Autodesk Fusion 360 part; units mm, degrees
(part 3 of 4)
sketch "Sketch4 (8)" plane through (0, 0, 0) normal (0, 0, 1) x (1, 0, 0) in component "PRT-HANGER"
  circle A0 centre (0, 0) radius 5.75
  dimension "d864" = 11.5
  constraint vertical A0.centre origin
  constraint horizontal A0.centre origin
  measures "d864" diameter of A0
extrude "Extrude4'''''''" cut sketch "Sketch4 (8)" along normal blind 8 from surface at -13 bodies 27 in component "PRT-HANGER"
sketch "Sketch5 (7)" plane through (0, 0, 0) normal (0, 0, 1) x (1, 0, 0) in component "PRT-HANGER"
  circle A0 centre (66, 0) radius 2
  dimension "d868" = 66
  dimension "d869" = 4
  constraint horizontal origin A0.centre
  measures "d868" horizontal distance of origin A0.centre
  measures "d869" diameter of A0
extrude "Extrude5''''''" cut sketch "Sketch5 (7)" along normal blind 14 from surface at -13 bodies 27 in component "PRT-HANGER"
sketch "Sketch6 (6)" plane through (0, 0, 0) normal (0, 0, 1) x (1, 0, 0) in component "PRT-HANGER"
  circle A0 centre (-66, 0) radius 2
  dimension "d873" = 66
  dimension "d874" = 4
  constraint horizontal origin A0.centre
  measures "d873" horizontal distance of origin A0.centre
  measures "d874" diameter of A0
extrude "Extrude6'''''" cut sketch "Sketch6 (6)" along normal blind 14 from surface at -13 bodies 27 in component "PRT-HANGER"
sketch "Sketch1 (14)" plane through (0, 0, 0) normal (1, 0, 0) x (0, 0, -1) in component "Sling cord"
  line L0 (-638.5, -1.5) -> (-638.5, 1.5)
  line L1 (-638.5, 1.5) -> (183, 101.5)
  line L2 (183, 101.5) -> (183, 98.5)
  line L3 (183, 98.5) -> (-638.5, -1.5)
  dimension "d878" = 638.5
  dimension "d880" = 1.5
  dimension "d881" = 1.5
  dimension "d882" = 101.5
  dimension "d883" = 98.5
  constraint vertical L0
  constraint vertical L2
  measures "d878" horizontal distance of origin L0.start
  measures "d880" vertical distance of origin L0.start
  measures "d881" vertical distance of origin L0.end
  measures "d882" vertical distance of origin L1.end
  measures "d883" vertical distance of origin L2.end
extrude "Extrude1''''''''''''''''''" add sketch "Sketch1 (14)" along normal blind 3 from surface at 64.5 separate body makes body 28 in component "Sling cord"
sketch "Sketch2 (11)" plane through (0, 0, 0) normal (1, 0, 0) x (0, 0, -1) in component "Sling cord"
  line L0 (-638.5, -1.5) -> (-638.5, 1.5)
  line L1 (-638.5, 1.5) -> (183, -98.5)
  line L2 (183, -98.5) -> (183, -101.5)
  line L3 (183, -101.5) -> (-638.5, -1.5)
  dimension "d887" = 638.5
  dimension "d889" = 1.5
  dimension "d890" = 1.5
  dimension "d891" = 98.5
  dimension "d892" = 101.5
  constraint vertical L0
  constraint vertical L2
  measures "d887" horizontal distance of origin L0.start
  measures "d889" vertical distance of origin L0.start
  measures "d890" vertical distance of origin L0.end
  measures "d891" vertical distance of origin L1.end
  measures "d892" vertical distance of origin L2.end
extrude "Extrude2''''''''''" add sketch "Sketch2 (11)" along normal blind 3 from surface at 64.5 separate body makes body 29 in component "Sling cord"
sketch "Sketch3 (9)" plane through (0, 0, 0) normal (1, 0, 0) x (0, 0, -1) in component "Sling cord"
  line L0 (-638.5, -1.5) -> (-638.5, 1.5)
  line L1 (-638.5, 1.5) -> (183, 101.5)
  line L2 (183, 101.5) -> (183, 98.5)
  line L3 (183, 98.5) -> (-638.5, -1.5)
  dimension "d896" = 638.5
  dimension "d898" = 1.5
  dimension "d899" = 1.5
  dimension "d900" = 101.5
  dimension "d901" = 98.5
  constraint vertical L0
  constraint vertical L2
  measures "d896" horizontal distance of origin L0.start
  measures "d898" vertical distance of origin L0.start
  measures "d899" vertical distance of origin L0.end
  measures "d900" vertical distance of origin L1.end
  measures "d901" vertical distance of origin L2.end
extrude "Extrude3''''''''" add sketch "Sketch3 (9)" along normal blind 3 from surface at -67.5 separate body makes body 30 in component "Sling cord"
sketch "Sketch4 (9)" plane through (0, 0, 0) normal (1, 0, 0) x (0, 0, -1) in component "Sling cord"
  line L0 (-638.5, -1.5) -> (-638.5, 1.5)
  line L1 (-638.5, 1.5) -> (183, -98.5)
  line L2 (183, -98.5) -> (183, -101.5)
  line L3 (183, -101.5) -> (-638.5, -1.5)
  dimension "d905" = 638.5
  dimension "d907" = 1.5
  dimension "d908" = 1.5
  dimension "d909" = 98.5
  dimension "d910" = 101.5
  constraint vertical L0
  constraint vertical L2
  measures "d905" horizontal distance of origin L0.start
  measures "d907" vertical distance of origin L0.start
  measures "d908" vertical distance of origin L0.end
  measures "d909" vertical distance of origin L1.end
  measures "d910" vertical distance of origin L2.end
extrude "Extrude4''''''''" add sketch "Sketch4 (9)" along normal blind 3 from surface at -67.5 separate body makes body 31 in component "Sling cord"
sketch "Sketch1 (15)" plane through (0, 0, 0) normal (0, 0, 1) x (1, 0, 0) in component "PRT-TRAY"
  line L0 (-70, -133) -> (70, -133)
  line L1 (70, -133) -> (70, 133)
  line L2 (70, 133) -> (-70, 133)
  line L3 (-70, 133) -> (-70, -133)
  dimension "d914" = 133
  dimension "d915" = 70
  dimension "d916" = 133
  dimension "d917" = 70
  constraint horizontal L0
  constraint vertical L1
  constraint horizontal L2
  constraint vertical L3
  measures "d914" vertical distance of origin L0.start
  measures "d915" horizontal distance of origin L0.end
  measures "d916" vertical distance of origin L1.end
  measures "d917" horizontal distance of origin L2.end
extrude "Extrude1'''''''''''''''''''" add sketch "Sketch1 (15)" along normal blind 8 separate body makes body 32 in component "PRT-TRAY"
sketch "Sketch2 (12)" plane through (0, 0, 0) normal (0, 0, 1) x (1, 0, 0) in component "PRT-TRAY"
  line L0 (50.3, 88.45) -> (58.3, 88.45)
  line L1 (58.3, 88.45) -> (58.3, 121.45)
  line L2 (58.3, 121.45) -> (50.3, 121.45)
  line L3 (50.3, 121.45) -> (50.3, 88.45)
  dimension "d920" = 88.45
  dimension "d921" = 58.3
  dimension "d922" = 121.45
  dimension "d923" = 50.3
  constraint horizontal L0
  constraint vertical L1
  constraint horizontal L2
  constraint vertical L3
  measures "d920" vertical distance of origin L0.start
  measures "d921" horizontal distance of origin L0.end
  measures "d922" vertical distance of origin L1.end
  measures "d923" horizontal distance of origin L2.end
extrude "Extrude2'''''''''''" add sketch "Sketch2 (12)" along normal blind 40 from surface at 8 bodies 32 in component "PRT-TRAY"
sketch "Sketch3 (10)" plane through (0, 0, 0) normal (0, 0, 1) x (1, 0, 0) in component "PRT-TRAY"
  line L0 (25.3, 113.45) -> (58.3, 113.45)
  line L1 (58.3, 113.45) -> (58.3, 121.45)
  line L2 (58.3, 121.45) -> (25.3, 121.45)
  line L3 (25.3, 121.45) -> (25.3, 113.45)
  dimension "d927" = 113.45
  dimension "d928" = 58.3
  dimension "d929" = 121.45
  dimension "d930" = 25.3
  constraint horizontal L0
  constraint vertical L1
  constraint horizontal L2
  constraint vertical L3
  measures "d927" vertical distance of origin L0.start
  measures "d928" horizontal distance of origin L0.end
  measures "d929" vertical distance of origin L1.end
  measures "d930" horizontal distance of origin L2.end
extrude "Extrude3'''''''''" add sketch "Sketch3 (10)" along normal blind 40 from surface at 8 bodies 32 in component "PRT-TRAY"
sketch "Sketch4 (10)" plane through (0, 0, 0) normal (0, 0, 1) x (1, 0, 0) in component "PRT-TRAY"
  circle A0 centre (66, 100) radius 2
  dimension "d934" = 66
  dimension "d935" = 100
  dimension "d936" = 4
  measures "d934" horizontal distance of origin A0.centre
  measures "d935" vertical distance of origin A0.centre
  measures "d936" diameter of A0
extrude "Extrude4'''''''''" cut sketch "Sketch4 (10)" along normal blind 10 from surface at -1 bodies 32 in component "PRT-TRAY"
sketch "Sketch5 (8)" plane through (0, 0, 0) normal (0, 0, 1) x (1, 0, 0) in component "PRT-TRAY"
  line L0 (50.3, -121.45) -> (58.3, -121.45)
  line L1 (58.3, -121.45) -> (58.3, -88.45)
  line L2 (58.3, -88.45) -> (50.3, -88.45)
  line L3 (50.3, -88.45) -> (50.3, -121.45)
  dimension "d940" = 121.45
  dimension "d941" = 58.3
  dimension "d942" = 88.45
  dimension "d943" = 50.3
  constraint horizontal L0
  constraint vertical L1
  constraint horizontal L2
  constraint vertical L3
  measures "d940" vertical distance of origin L0.start
  measures "d941" horizontal distance of origin L0.end
  measures "d942" vertical distance of origin L1.end
  measures "d943" horizontal distance of origin L2.end
extrude "Extrude5'''''''" add sketch "Sketch5 (8)" along normal blind 40 from surface at 8 bodies 32 in component "PRT-TRAY"
sketch "Sketch6 (7)" plane through (0, 0, 0) normal (0, 0, 1) x (1, 0, 0) in component "PRT-TRAY"
  line L0 (25.3, -121.45) -> (58.3, -121.45)
  line L1 (58.3, -121.45) -> (58.3, -113.45)
  line L2 (58.3, -113.45) -> (25.3, -113.45)
  line L3 (25.3, -113.45) -> (25.3, -121.45)
  dimension "d947" = 121.45
  dimension "d948" = 58.3
  dimension "d949" = 113.45
  dimension "d950" = 25.3
  constraint horizontal L0
  constraint vertical L1
  constraint horizontal L2
  constraint vertical L3
  measures "d947" vertical distance of origin L0.start
  measures "d948" horizontal distance of origin L0.end
  measures "d949" vertical distance of origin L1.end
  measures "d950" horizontal distance of origin L2.end
extrude "Extrude6''''''" add sketch "Sketch6 (7)" along normal blind 40 from surface at 8 bodies 32 in component "PRT-TRAY"
sketch "Sketch7 (6)" plane through (0, 0, 0) normal (0, 0, 1) x (1, 0, 0) in component "PRT-TRAY"
  circle A0 centre (66, -100) radius 2
  dimension "d954" = 66
  dimension "d955" = 100
  dimension "d956" = 4
  measures "d954" horizontal distance of origin A0.centre
  measures "d955" vertical distance of origin A0.centre
  measures "d956" diameter of A0
extrude "Extrude7'''''" cut sketch "Sketch7 (6)" along normal blind 10 from surface at -1 bodies 32 in component "PRT-TRAY"
sketch "Sketch8 (6)" plane through (0, 0, 0) normal (0, 0, 1) x (1, 0, 0) in component "PRT-TRAY"
  line L0 (-58.3, 88.45) -> (-50.3, 88.45)
  line L1 (-50.3, 88.45) -> (-50.3, 121.45)
  line L2 (-50.3, 121.45) -> (-58.3, 121.45)
  line L3 (-58.3, 121.45) -> (-58.3, 88.45)
  dimension "d960" = 88.45
  dimension "d961" = 50.3
  dimension "d962" = 121.45
  dimension "d963" = 58.3
  constraint horizontal L0
  constraint vertical L1
  constraint horizontal L2
  constraint vertical L3
  measures "d960" vertical distance of origin L0.start
  measures "d961" horizontal distance of origin L0.end
  measures "d962" vertical distance of origin L1.end
  measures "d963" horizontal distance of origin L2.end
extrude "Extrude8'''''" add sketch "Sketch8 (6)" along normal blind 40 from surface at 8 bodies 32 in component "PRT-TRAY"
sketch "Sketch9 (3)" plane through (0, 0, 0) normal (0, 0, 1) x (1, 0, 0) in component "PRT-TRAY"
  line L0 (-58.3, 113.45) -> (-25.3, 113.45)
  line L1 (-25.3, 113.45) -> (-25.3, 121.45)
  line L2 (-25.3, 121.45) -> (-58.3, 121.45)
  line L3 (-58.3, 121.45) -> (-58.3, 113.45)
  dimension "d967" = 113.45
  dimension "d968" = 25.3
  dimension "d969" = 121.45
  dimension "d970" = 58.3
  constraint horizontal L0
  constraint vertical L1
  constraint horizontal L2
  constraint vertical L3
  measures "d967" vertical distance of origin L0.start
  measures "d968" horizontal distance of origin L0.end
  measures "d969" vertical distance of origin L1.end
  measures "d970" horizontal distance of origin L2.end
extrude "Extrude9''" add sketch "Sketch9 (3)" along normal blind 40 from surface at 8 bodies 32 in component "PRT-TRAY"
sketch "Sketch10 (3)" plane through (0, 0, 0) normal (0, 0, 1) x (1, 0, 0) in component "PRT-TRAY"
  circle A0 centre (-66, 100) radius 2
  dimension "d974" = 66
  dimension "d975" = 100
  dimension "d976" = 4
  measures "d974" horizontal distance of origin A0.centre
  measures "d975" vertical distance of origin A0.centre
  measures "d976" diameter of A0
extrude "Extrude10''" cut sketch "Sketch10 (3)" along normal blind 10 from surface at -1 bodies 32 in component "PRT-TRAY"
sketch "Sketch11 (3)" plane through (0, 0, 0) normal (0, 0, 1) x (1, 0, 0) in component "PRT-TRAY"
  line L0 (-58.3, -121.45) -> (-50.3, -121.45)
  line L1 (-50.3, -121.45) -> (-50.3, -88.45)
  line L2 (-50.3, -88.45) -> (-58.3, -88.45)
  line L3 (-58.3, -88.45) -> (-58.3, -121.45)
  dimension "d980" = 121.45
  dimension "d981" = 50.3
  dimension "d982" = 88.45
  dimension "d983" = 58.3
  constraint horizontal L0
  constraint vertical L1
  constraint horizontal L2
  constraint vertical L3
  measures "d980" vertical distance of origin L0.start
  measures "d981" horizontal distance of origin L0.end
  measures "d982" vertical distance of origin L1.end
  measures "d983" horizontal distance of origin L2.end
extrude "Extrude11''" add sketch "Sketch11 (3)" along normal blind 40 from surface at 8 bodies 32 in component "PRT-TRAY"
sketch "Sketch12 (3)" plane through (0, 0, 0) normal (0, 0, 1) x (1, 0, 0) in component "PRT-TRAY"
  line L0 (-58.3, -121.45) -> (-25.3, -121.45)
  line L1 (-25.3, -121.45) -> (-25.3, -113.45)
  line L2 (-25.3, -113.45) -> (-58.3, -113.45)
  line L3 (-58.3, -113.45) -> (-58.3, -121.45)
  dimension "d987" = 121.45
  dimension "d988" = 25.3
  dimension "d989" = 113.45
  dimension "d990" = 58.3
  constraint horizontal L0
  constraint vertical L1
  constraint horizontal L2
  constraint vertical L3
  measures "d987" vertical distance of origin L0.start
  measures "d988" horizontal distance of origin L0.end
  measures "d989" vertical distance of origin L1.end
  measures "d990" horizontal distance of origin L2.end
extrude "Extrude12''" add sketch "Sketch12 (3)" along normal blind 40 from surface at 8 bodies 32 in component "PRT-TRAY"
sketch "Sketch13 (3)" plane through (0, 0, 0) normal (0, 0, 1) x (1, 0, 0) in component "PRT-TRAY"
  circle A0 centre (-66, -100) radius 2
  dimension "d994" = 66
  dimension "d995" = 100
  dimension "d996" = 4
  measures "d994" horizontal distance of origin A0.centre
  measures "d995" vertical distance of origin A0.centre
  measures "d996" diameter of A0
extrude "Extrude13''" cut sketch "Sketch13 (3)" along normal blind 10 from surface at -1 bodies 32 in component "PRT-TRAY"
sketch "Sketch1 (16)" plane through (0, 0, 0) normal (0, 0, 1) x (1, 0, 0) in component "6U envelope (reference)"
  line L0 (-50, -113.15) -> (50, -113.15)
  line L1 (50, -113.15) -> (50, 113.15)
  line L2 (50, 113.15) -> (-50, 113.15)
  line L3 (-50, 113.15) -> (-50, -113.15)
  dimension "d1000" = 113.15
  dimension "d1001" = 50
  dimension "d1002" = 113.15
  dimension "d1003" = 50
  constraint horizontal L0
  constraint vertical L1
  constraint horizontal L2
  constraint vertical L3
  measures "d1000" vertical distance of origin L0.start
  measures "d1001" horizontal distance of origin L0.end
  measures "d1002" vertical distance of origin L1.end
  measures "d1003" horizontal distance of origin L2.end
extrude "Extrude1''''''''''''''''''''" add sketch "Sketch1 (16)" along normal blind 366 from surface at -183 separate body makes body 33 in component "6U envelope (reference)"
sketch "Sketch1 (17)" plane through (0, 0, 0) normal (0, 0, 1) x (1, 0, 0) in component "Working volume 6U+10 (reference)"
  line L0 (-60, -123.15) -> (60, -123.15)
  line L1 (60, -123.15) -> (60, 123.15)
  line L2 (60, 123.15) -> (-60, 123.15)
  line L3 (-60, 123.15) -> (-60, -123.15)
  dimension "d1007" = 123.15
  dimension "d1008" = 60
  dimension "d1009" = 123.15
  dimension "d1010" = 60
  constraint horizontal L0
  constraint vertical L1
  constraint horizontal L2
  constraint vertical L3
  measures "d1007" vertical distance of origin L0.start
  measures "d1008" horizontal distance of origin L0.end
  measures "d1009" vertical distance of origin L1.end
  measures "d1010" horizontal distance of origin L2.end
extrude "Extrude1'''''''''''''''''''''" add sketch "Sketch1 (17)" along normal blind 386 from surface at -193 separate body makes body 34 in component "Working volume 6U+10 (reference)"
sketch "Sketch1 (18)" plane through (0, 0, 0) normal (0, 0, 1) x (1, 0, 0) in component "PRT-GAUGE-X"
  line L0 (0, -20) -> (251.25, -20)
  line L1 (251.25, -20) -> (251.25, 20)
  line L2 (251.25, 20) -> (0, 20)
  line L3 (0, 20) -> (0, -20)
  dimension "d1014" = 20
  dimension "d1015" = 251.25
  dimension "d1016" = 20
  constraint horizontal L0
  constraint vertical L1
  constraint horizontal L2
  constraint vertical L3
  constraint vertical origin L2.end
  measures "d1014" vertical distance of origin L0.start
  measures "d1015" horizontal distance of origin L0.end
  measures "d1016" vertical distance of origin L1.end
extrude "Extrude1''''''''''''''''''''''" add sketch "Sketch1 (18)" along normal blind 10 separate body makes body 35 in component "PRT-GAUGE-X"
sketch "Sketch2 (13)" plane through (0, 0, 0) normal (0, 0, 1) x (1, 0, 0) in component "PRT-GAUGE-X"
  line L0 (0, -3.8) -> (251.25, -3.8)
  line L1 (251.25, -3.8) -> (251.25, 3.8)
  line L2 (251.25, 3.8) -> (0, 3.8)
  line L3 (0, 3.8) -> (0, -3.8)
  dimension "d1019" = 3.8
  dimension "d1020" = 251.25
  dimension "d1021" = 3.8
  constraint horizontal L0
  constraint vertical L1
  constraint horizontal L2
  constraint vertical L3
  constraint vertical origin L2.end
  measures "d1019" vertical distance of origin L0.start
  measures "d1020" horizontal distance of origin L0.end
  measures "d1021" vertical distance of origin L1.end
extrude "Extrude2''''''''''''" add sketch "Sketch2 (13)" along normal blind 3.8 from surface at -3.8 bodies 35 in component "PRT-GAUGE-X"
sketch "Sketch1 (19)" plane through (0, 0, 0) normal (0, 0, 1) x (1, 0, 0) in component "PRT-GAUGE-Y"
  line L0 (0, -20) -> (271, -20)
  line L1 (271, -20) -> (271, 20)
  line L2 (271, 20) -> (0, 20)
  line L3 (0, 20) -> (0, -20)
  dimension "d1025" = 20
  dimension "d1026" = 271
  dimension "d1027" = 20
  constraint horizontal L0
  constraint vertical L1
  constraint horizontal L2
  constraint vertical L3
  constraint vertical origin L2.end
  measures "d1025" vertical distance of origin L0.start
  measures "d1026" horizontal distance of origin L0.end
  measures "d1027" vertical distance of origin L1.end
extrude "Extrude1'''''''''''''''''''''''" add sketch "Sketch1 (19)" along normal blind 10 separate body makes body 36 in component "PRT-GAUGE-Y"
sketch "Sketch2 (14)" plane through (0, 0, 0) normal (0, 0, 1) x (1, 0, 0) in component "PRT-GAUGE-Y"
  line L0 (0, -3.8) -> (271, -3.8)
  line L1 (271, -3.8) -> (271, 3.8)
  line L2 (271, 3.8) -> (0, 3.8)
  line L3 (0, 3.8) -> (0, -3.8)
  dimension "d1030" = 3.8
  dimension "d1031" = 271
  dimension "d1032" = 3.8
  constraint horizontal L0
  constraint vertical L1
  constraint horizontal L2
  constraint vertical L3
  constraint vertical origin L2.end
  measures "d1030" vertical distance of origin L0.start
  measures "d1031" horizontal distance of origin L0.end
  measures "d1032" vertical distance of origin L1.end
extrude "Extrude2'''''''''''''" add sketch "Sketch2 (14)" along normal blind 3.8 from surface at -3.8 bodies 36 in component "PRT-GAUGE-Y"
sketch "Sketch1 (20)" plane through (0, 0, 0) normal (0, 0, 1) x (1, 0, 0) in component "PRT-GAUGE-Z"
  line L0 (0, -20) -> (187.5, -20)
  line L1 (187.5, -20) -> (187.5, 20)
  line L2 (187.5, 20) -> (0, 20)
  line L3 (0, 20) -> (0, -20)
  dimension "d1036" = 20
  dimension "d1037" = 187.5
  dimension "d1038" = 20
  constraint horizontal L0
  constraint vertical L1
  constraint horizontal L2
  constraint vertical L3
  constraint vertical origin L2.end
  measures "d1036" vertical distance of origin L0.start
  measures "d1037" horizontal distance of origin L0.end
  measures "d1038" vertical distance of origin L1.end
extrude "Extrude1''''''''''''''''''''''''" add sketch "Sketch1 (20)" along normal blind 10 separate body makes body 37 in component "PRT-GAUGE-Z"
sketch "Sketch2 (15)" plane through (0, 0, 0) normal (0, 0, 1) x (1, 0, 0) in component "PRT-GAUGE-Z"
  line L0 (0, -3.8) -> (187.5, -3.8)
  line L1 (187.5, -3.8) -> (187.5, 3.8)
  line L2 (187.5, 3.8) -> (0, 3.8)
  line L3 (0, 3.8) -> (0, -3.8)
  dimension "d1041" = 3.8
  dimension "d1042" = 187.5
  dimension "d1043" = 3.8
  constraint horizontal L0
  constraint vertical L1
  constraint horizontal L2
  constraint vertical L3
  constraint vertical origin L2.end
  measures "d1041" vertical distance of origin L0.start
  measures "d1042" horizontal distance of origin L0.end
  measures "d1043" vertical distance of origin L1.end
extrude "Extrude2''''''''''''''" add sketch "Sketch2 (15)" along normal blind 3.8 from surface at -3.8 bodies 37 in component "PRT-GAUGE-Z"
sketch "Sketch1 (21)" plane through (0, 0, 0) normal (0, 0, 1) x (1, 0, 0) in component "PRT-GAUGE-C"
  line L0 (0, -20) -> (187, -20)
  line L1 (187, -20) -> (187, 20)
  line L2 (187, 20) -> (0, 20)
  line L3 (0, 20) -> (0, -20)
  dimension "d1047" = 20
  dimension "d1048" = 187
  dimension "d1049" = 20
  constraint horizontal L0
  constraint vertical L1
  constraint horizontal L2
  constraint vertical L3
  constraint vertical origin L2.end
  measures "d1047" vertical distance of origin L0.start
  measures "d1048" horizontal distance of origin L0.end
  measures "d1049" vertical distance of origin L1.end
extrude "Extrude1'''''''''''''''''''''''''" add sketch "Sketch1 (21)" along normal blind 10 separate body makes body 38 in component "PRT-GAUGE-C"
sketch "Sketch2 (16)" plane through (0, 0, 0) normal (0, 0, 1) x (1, 0, 0) in component "PRT-GAUGE-C"
  line L0 (0, -3.8) -> (187, -3.8)
  line L1 (187, -3.8) -> (187, 3.8)
  line L2 (187, 3.8) -> (0, 3.8)
  line L3 (0, 3.8) -> (0, -3.8)
  dimension "d1052" = 3.8
  dimension "d1053" = 187
  dimension "d1054" = 3.8
  constraint horizontal L0
  constraint vertical L1
  constraint horizontal L2
  constraint vertical L3
  constraint vertical origin L2.end
  measures "d1052" vertical distance of origin L0.start
  measures "d1053" horizontal distance of origin L0.end
  measures "d1054" vertical distance of origin L1.end
extrude "Extrude2'''''''''''''''" add sketch "Sketch2 (16)" along normal blind 3.8 from surface at -3.8 bodies 38 in component "PRT-GAUGE-C"
ref_plane "WorkPlane1" through (0, 383.5, 0) normal (0, 1, 0) x (0, 0, 1)
ref_plane "WorkPlane2" through (0, 0, 425) normal (0, 0, 1) x (1, 0, 0)
component "6575N25 cross-section" placed x (1, 0, 0) y (0, 1, 0) z (0, 0, 1) at (0, 0, 0)
component "Pair X" placed x (1, 0, 0) y (0, 1, 0) z (0, 0, 1) at (0, 0, 0)
component "Pair Y" placed x (1, 0, 0) y (0, 1, 0) z (0, 0, 1) at (0, 0, 0)
component "Pair Z" placed x (1, 0, 0) y (0, 1, 0) z (0, 0, 1) at (0, 0, 0)
component "Crossing mounts" placed x (1, 0, 0) y (0, 1, 0) z (0, 0, 1) at (0, 0, 0)
component "Stand" placed x (1, 0, 0) y (0, 1, 0) z (0, 0, 1) at (0, 0, 0)
component "CubeSat hanger" placed x (1, 0, 0) y (0, 1, 0) z (0, 0, 1) at (0, 0, 0)
component "Reference (not built)" placed x (1, 0, 0) y (0, 1, 0) z (0, 0, 1) at (0, 0, 0)
component "Assembly gauges (removable)" placed x (1, 0, 0) y (0, 1, 0) z (0, 0, 1) at (0, 0, 0)
component "Coil X" placed x (1, 0, 0) y (0, 1, 0) z (0, 0, 1) at (0, 0, 0) in component "Pair X"
component "Coil X" placed x (1, 0, 0) y (0, 1, 0) z (0, 0, 1) at (0, 0, 0) in component "Pair X"
component "6575N25 x 1301" placed x (1, 0, 0) y (0, 1, 0) z (0, 0, 1) at (0, 0, 0) in component "Coil X"
component "6575N25 x 1301" placed x (1, 0, 0) y (0, 1, 0) z (0, 0, 1) at (0, 0, 0) in component "Coil X"
component "6575N25 x 1301" placed x (1, 0, 0) y (0, 1, 0) z (0, 0, 1) at (0, 0, 0) in component "Coil X"
component "6575N25 x 1301" placed x (1, 0, 0) y (0, 1, 0) z (0, 0, 1) at (0, 0, 0) in component "Coil X"
component "PRT-CORNER-STEP" placed x (1, 0, 0) y (0, 1, 0) z (0, 0, 1) at (0, 0, 0) in component "Coil X"
component "5537T586" placed x (1, 0, 0) y (0, 1, 0) z (0, 0, 1) at (0, 0, 0) in component "Coil X"
component "PRT-CORNER" placed x (1, 0, 0) y (0, 1, 0) z (0, 0, 1) at (0, 0, 0) in component "Coil X"
component "5537T586" placed x (1, 0, 0) y (0, 1, 0) z (0, 0, 1) at (0, 0, 0) in component "Coil X"
component "PRT-CORNER" placed x (1, 0, 0) y (0, 1, 0) z (0, 0, 1) at (0, 0, 0) in component "Coil X"
component "5537T586" placed x (1, 0, 0) y (0, 1, 0) z (0, 0, 1) at (0, 0, 0) in component "Coil X"
component "PRT-CORNER" placed x (1, 0, 0) y (0, 1, 0) z (0, 0, 1) at (0, 0, 0) in component "Coil X"
component "5537T586" placed x (1, 0, 0) y (0, 1, 0) z (0, 0, 1) at (0, 0, 0) in component "Coil X"
component "Winding X (40 t AWG18)" placed x (1, 0, 0) y (0, 1, 0) z (0, 0, 1) at (0, 0, 0) in component "Coil X"
component "PRT-CLIP" placed x (1, 0, 0) y (0, 1, 0) z (0, 0, 1) at (0, 0, 0) in component "Coil X"
component "PRT-CLIP" placed x (1, 0, 0) y (0, 1, 0) z (0, 0, 1) at (0, 0, 0) in component "Coil X"
component "PRT-CLIP" placed x (1, 0, 0) y (0, 1, 0) z (0, 0, 1) at (0, 0, 0) in component "Coil X"
component "PRT-CLIP" placed x (1, 0, 0) y (0, 1, 0) z (0, 0, 1) at (0, 0, 0) in component "Coil X"
component "PRT-CLIP" placed x (1, 0, 0) y (0, 1, 0) z (0, 0, 1) at (0, 0, 0) in component "Coil X"
component "PRT-CLIP" placed x (1, 0, 0) y (0, 1, 0) z (0, 0, 1) at (0, 0, 0) in component "Coil X"
component "PRT-CLIP" placed x (1, 0, 0) y (0, 1, 0) z (0, 0, 1) at (0, 0, 0) in component "Coil X"
component "PRT-CLIP" placed x (1, 0, 0) y (0, 1, 0) z (0, 0, 1) at (0, 0, 0) in component "Coil X"
component "PRT-CLIP" placed x (1, 0, 0) y (0, 1, 0) z (0, 0, 1) at (0, 0, 0) in component "Coil X"
component "PRT-CLIP" placed x (1, 0, 0) y (0, 1, 0) z (0, 0, 1) at (0, 0, 0) in component "Coil X"
component "PRT-CLIP" placed x (1, 0, 0) y (0, 1, 0) z (0, 0, 1) at (0, 0, 0) in component "Coil X"
component "PRT-CLIP" placed x (1, 0, 0) y (0, 1, 0) z (0, 0, 1) at (0, 0, 0) in component "Coil X"
component "Leads X" placed x (1, 0, 0) y (0, 1, 0) z (0, 0, 1) at (0, 0, 0) in component "Coil X"
component "PRT-TIE" placed x (1, 0, 0) y (0, 1, 0) z (0, 0, 1) at (0, 0, 0) in component "Leads X"
component "Anderson 1327G6" placed x (1, 0, 0) y (0, 1, 0) z (0, 0, 1) at (0, 0, 0) in component "Leads X"
component "Anderson 1327" placed x (1, 0, 0) y (0, 1, 0) z (0, 0, 1) at (0, 0, 0) in component "Leads X"
component "Coil Y" placed x (1, 0, 0) y (0, 1, 0) z (0, 0, 1) at (0, 0, 0) in component "Pair Y"
component "Coil Y" placed x (1, 0, 0) y (0, 1, 0) z (0, 0, 1) at (0, 0, 0) in component "Pair Y"
component "6575N25 x 1385" placed x (1, 0, 0) y (0, 1, 0) z (0, 0, 1) at (0, 0, 0) in component "Coil Y"
component "6575N25 x 1385" placed x (1, 0, 0) y (0, 1, 0) z (0, 0, 1) at (0, 0, 0) in component "Coil Y"
component "6575N25 x 1385" placed x (1, 0, 0) y (0, 1, 0) z (0, 0, 1) at (0, 0, 0) in component "Coil Y"
component "6575N25 x 1385" placed x (1, 0, 0) y (0, 1, 0) z (0, 0, 1) at (0, 0, 0) in component "Coil Y"
component "PRT-CORNER-STEP" placed x (1, 0, 0) y (0, 1, 0) z (0, 0, 1) at (0, 0, 0) in component "Coil Y"
component "5537T586" placed x (1, 0, 0) y (0, 1, 0) z (0, 0, 1) at (0, 0, 0) in component "Coil Y"
component "PRT-CORNER" placed x (1, 0, 0) y (0, 1, 0) z (0, 0, 1) at (0, 0, 0) in component "Coil Y"
component "5537T586" placed x (1, 0, 0) y (0, 1, 0) z (0, 0, 1) at (0, 0, 0) in component "Coil Y"
component "PRT-CORNER" placed x (1, 0, 0) y (0, 1, 0) z (0, 0, 1) at (0, 0, 0) in component "Coil Y"
component "5537T586" placed x (1, 0, 0) y (0, 1, 0) z (0, 0, 1) at (0, 0, 0) in component "Coil Y"
component "PRT-CORNER" placed x (1, 0, 0) y (0, 1, 0) z (0, 0, 1) at (0, 0, 0) in component "Coil Y"
component "5537T586" placed x (1, 0, 0) y (0, 1, 0) z (0, 0, 1) at (0, 0, 0) in component "Coil Y"
component "Winding Y (40 t AWG18)" placed x (1, 0, 0) y (0, 1, 0) z (0, 0, 1) at (0, 0, 0) in component "Coil Y"
component "PRT-CLIP" placed x (1, 0, 0) y (0, 1, 0) z (0, 0, 1) at (0, 0, 0) in component "Coil Y"
component "PRT-CLIP" placed x (1, 0, 0) y (0, 1, 0) z (0, 0, 1) at (0, 0, 0) in component "Coil Y"
component "PRT-CLIP" placed x (1, 0, 0) y (0, 1, 0) z (0, 0, 1) at (0, 0, 0) in component "Coil Y"
component "PRT-CLIP" placed x (1, 0, 0) y (0, 1, 0) z (0, 0, 1) at (0, 0, 0) in component "Coil Y"
component "PRT-CLIP" placed x (1, 0, 0) y (0, 1, 0) z (0, 0, 1) at (0, 0, 0) in component "Coil Y"
component "PRT-CLIP" placed x (1, 0, 0) y (0, 1, 0) z (0, 0, 1) at (0, 0, 0) in component "Coil Y"
component "PRT-CLIP" placed x (1, 0, 0) y (0, 1, 0) z (0, 0, 1) at (0, 0, 0) in component "Coil Y"
component "PRT-CLIP" placed x (1, 0, 0) y (0, 1, 0) z (0, 0, 1) at (0, 0, 0) in component "Coil Y"
component "PRT-CLIP" placed x (1, 0, 0) y (0, 1, 0) z (0, 0, 1) at (0, 0, 0) in component "Coil Y"
component "PRT-CLIP" placed x (1, 0, 0) y (0, 1, 0) z (0, 0, 1) at (0, 0, 0) in component "Coil Y"
component "PRT-CLIP" placed x (1, 0, 0) y (0, 1, 0) z (0, 0, 1) at (0, 0, 0) in component "Coil Y"
component "PRT-CLIP" placed x (1, 0, 0) y (0, 1, 0) z (0, 0, 1) at (0, 0, 0) in component "Coil Y"
component "Leads Y" placed x (1, 0, 0) y (0, 1, 0) z (0, 0, 1) at (0, 0, 0) in component "Coil Y"
component "PRT-TIE" placed x (1, 0, 0) y (0, 1, 0) z (0, 0, 1) at (0, 0, 0) in component "Leads Y"
component "Anderson 1327G6" placed x (1, 0, 0) y (0, 1, 0) z (0, 0, 1) at (0, 0, 0) in component "Leads Y"
component "Anderson 1327" placed x (1, 0, 0) y (0, 1, 0) z (0, 0, 1) at (0, 0, 0) in component "Leads Y"
component "Coil Z" placed x (1, 0, 0) y (0, 1, 0) z (0, 0, 1) at (0, 0, 0) in component "Pair Z"
component "Coil Z" placed x (1, 0, 0) y (0, 1, 0) z (0, 0, 1) at (0, 0, 0) in component "Pair Z"
component "6575N25 x 1469" placed x (1, 0, 0) y (0, 1, 0) z (0, 0, 1) at (0, 0, 0) in component "Coil Z"
component "6575N25 x 1469" placed x (1, 0, 0) y (0, 1, 0) z (0, 0, 1) at (0, 0, 0) in component "Coil Z"
component "6575N25 x 1469" placed x (1, 0, 0) y (0, 1, 0) z (0, 0, 1) at (0, 0, 0) in component "Coil Z"
component "6575N25 x 1469" placed x (1, 0, 0) y (0, 1, 0) z (0, 0, 1) at (0, 0, 0) in component "Coil Z"
component "PRT-CORNER-STEP" placed x (1, 0, 0) y (0, 1, 0) z (0, 0, 1) at (0, 0, 0) in component "Coil Z"
component "5537T586" placed x (1, 0, 0) y (0, 1, 0) z (0, 0, 1) at (0, 0, 0) in component "Coil Z"
component "PRT-CORNER" placed x (1, 0, 0) y (0, 1, 0) z (0, 0, 1) at (0, 0, 0) in component "Coil Z"
component "5537T586" placed x (1, 0, 0) y (0, 1, 0) z (0, 0, 1) at (0, 0, 0) in component "Coil Z"
component "PRT-CORNER" placed x (1, 0, 0) y (0, 1, 0) z (0, 0, 1) at (0, 0, 0) in component "Coil Z"
component "5537T586" placed x (1, 0, 0) y (0, 1, 0) z (0, 0, 1) at (0, 0, 0) in component "Coil Z"
component "PRT-CORNER" placed x (1, 0, 0) y (0, 1, 0) z (0, 0, 1) at (0, 0, 0) in component "Coil Z"
component "5537T586" placed x (1, 0, 0) y (0, 1, 0) z (0, 0, 1) at (0, 0, 0) in component "Coil Z"
component "Winding Z (40 t AWG18)" placed x (1, 0, 0) y (0, 1, 0) z (0, 0, 1) at (0, 0, 0) in component "Coil Z"
component "PRT-CLIP" placed x (1, 0, 0) y (0, 1, 0) z (0, 0, 1) at (0, 0, 0) in component "Coil Z"
component "PRT-CLIP" placed x (1, 0, 0) y (0, 1, 0) z (0, 0, 1) at (0, 0, 0) in component "Coil Z"
component "PRT-CLIP" placed x (1, 0, 0) y (0, 1, 0) z (0, 0, 1) at (0, 0, 0) in component "Coil Z"
component "PRT-CLIP" placed x (1, 0, 0) y (0, 1, 0) z (0, 0, 1) at (0, 0, 0) in component "Coil Z"
component "PRT-CLIP" placed x (1, 0, 0) y (0, 1, 0) z (0, 0, 1) at (0, 0, 0) in component "Coil Z"
component "PRT-CLIP" placed x (1, 0, 0) y (0, 1, 0) z (0, 0, 1) at (0, 0, 0) in component "Coil Z"
component "PRT-CLIP" placed x (1, 0, 0) y (0, 1, 0) z (0, 0, 1) at (0, 0, 0) in component "Coil Z"
component "PRT-CLIP" placed x (1, 0, 0) y (0, 1, 0) z (0, 0, 1) at (0, 0, 0) in component "Coil Z"
component "PRT-CLIP" placed x (1, 0, 0) y (0, 1, 0) z (0, 0, 1) at (0, 0, 0) in component "Coil Z"
component "PRT-CLIP" placed x (1, 0, 0) y (0, 1, 0) z (0, 0, 1) at (0, 0, 0) in component "Coil Z"
component "PRT-CLIP" placed x (1, 0, 0) y (0, 1, 0) z (0, 0, 1) at (0, 0, 0) in component "Coil Z"
component "PRT-CLIP" placed x (1, 0, 0) y (0, 1, 0) z (0, 0, 1) at (0, 0, 0) in component "Coil Z"
component "Leads Z" placed x (1, 0, 0) y (0, 1, 0) z (0, 0, 1) at (0, 0, 0) in component "Coil Z"
component "PRT-TIE" placed x (1, 0, 0) y (0, 1, 0) z (0, 0, 1) at (0, 0, 0) in component "Leads Z"
component "Anderson 1327G6" placed x (1, 0, 0) y (0, 1, 0) z (0, 0, 1) at (0, 0, 0) in component "Leads Z"
component "Anderson 1327" placed x (1, 0, 0) y (0, 1, 0) z (0, 0, 1) at (0, 0, 0) in component "Leads Z"
component "5537T586" placed x (1, 0, 0) y (0, 1, 0) z (0, 0, 1) at (0, 0, 0) in component "Crossing mounts"
component "PRT-SHIM" placed x (1, 0, 0) y (0, 1, 0) z (0, 0, 1) at (0, 0, 0) in component "Crossing mounts"
component "5537T586" placed x (1, 0, 0) y (0, 1, 0) z (0, 0, 1) at (0, 0, 0) in component "Crossing mounts"
component "PRT-SHIM" placed x (1, 0, 0) y (0, 1, 0) z (0, 0, 1) at (0, 0, 0) in component "Crossing mounts"
component "5537T586" placed x (1, 0, 0) y (0, 1, 0) z (0, 0, 1) at (0, 0, 0) in component "Crossing mounts"
component "PRT-SHIM" placed x (1, 0, 0) y (0, 1, 0) z (0, 0, 1) at (0, 0, 0) in component "Crossing mounts"
component "5537T586" placed x (1, 0, 0) y (0, 1, 0) z (0, 0, 1) at (0, 0, 0) in component "Crossing mounts"
component "PRT-SHIM" placed x (1, 0, 0) y (0, 1, 0) z (0, 0, 1) at (0, 0, 0) in component "Crossing mounts"
component "5537T586" placed x (1, 0, 0) y (0, 1, 0) z (0, 0, 1) at (0, 0, 0) in component "Crossing mounts"
component "PRT-SHIM" placed x (1, 0, 0) y (0, 1, 0) z (0, 0, 1) at (0, 0, 0) in component "Crossing mounts"
component "5537T586" placed x (1, 0, 0) y (0, 1, 0) z (0, 0, 1) at (0, 0, 0) in component "Crossing mounts"
component "PRT-SHIM" placed x (1, 0, 0) y (0, 1, 0) z (0, 0, 1) at (0, 0, 0) in component "Crossing mounts"
component "5537T586" placed x (1, 0, 0) y (0, 1, 0) z (0, 0, 1) at (0, 0, 0) in component "Crossing mounts"
component "PRT-SHIM" placed x (1, 0, 0) y (0, 1, 0) z (0, 0, 1) at (0, 0, 0) in component "Crossing mounts"
component "5537T586" placed x (1, 0, 0) y (0, 1, 0) z (0, 0, 1) at (0, 0, 0) in component "Crossing mounts"
component "PRT-SHIM" placed x (1, 0, 0) y (0, 1, 0) z (0, 0, 1) at (0, 0, 0) in component "Crossing mounts"
component "5537T586" placed x (1, 0, 0) y (0, 1, 0) z (0, 0, 1) at (0, 0, 0) in component "Crossing mounts"
component "PRT-SHIM" placed x (1, 0, 0) y (0, 1, 0) z (0, 0, 1) at (0, 0, 0) in component "Crossing mounts"
component "5537T586" placed x (1, 0, 0) y (0, 1, 0) z (0, 0, 1) at (0, 0, 0) in component "Crossing mounts"
component "PRT-SHIM" placed x (1, 0, 0) y (0, 1, 0) z (0, 0, 1) at (0, 0, 0) in component "Crossing mounts"
component "5537T586" placed x (1, 0, 0) y (0, 1, 0) z (0, 0, 1) at (0, 0, 0) in component "Crossing mounts"
component "PRT-SHIM" placed x (1, 0, 0) y (0, 1, 0) z (0, 0, 1) at (0, 0, 0) in component "Crossing mounts"
component "5537T586" placed x (1, 0, 0) y (0, 1, 0) z (0, 0, 1) at (0, 0, 0) in component "Crossing mounts"
component "PRT-SHIM" placed x (1, 0, 0) y (0, 1, 0) z (0, 0, 1) at (0, 0, 0) in component "Crossing mounts"
component "5537T586" placed x (1, 0, 0) y (0, 1, 0) z (0, 0, 1) at (0, 0, 0) in component "Crossing mounts"
component "PRT-SHIM" placed x (1, 0, 0) y (0, 1, 0) z (0, 0, 1) at (0, 0, 0) in component "Crossing mounts"
component "5537T586" placed x (1, 0, 0) y (0, 1, 0) z (0, 0, 1) at (0, 0, 0) in component "Crossing mounts"
component "PRT-SHIM" placed x (1, 0, 0) y (0, 1, 0) z (0, 0, 1) at (0, 0, 0) in component "Crossing mounts"
component "5537T586" placed x (1, 0, 0) y (0, 1, 0) z (0, 0, 1) at (0, 0, 0) in component "Crossing mounts"
component "PRT-SHIM" placed x (1, 0, 0) y (0, 1, 0) z (0, 0, 1) at (0, 0, 0) in component "Crossing mounts"
component "5537T586" placed x (1, 0, 0) y (0, 1, 0) z (0, 0, 1) at (0, 0, 0) in component "Crossing mounts"
component "PRT-SHIM" placed x (1, 0, 0) y (0, 1, 0) z (0, 0, 1) at (0, 0, 0) in component "Crossing mounts"
component "5537T586" placed x (1, 0, 0) y (0, 1, 0) z (0, 0, 1) at (0, 0, 0) in component "Crossing mounts"
component "PRT-SHIM" placed x (1, 0, 0) y (0, 1, 0) z (0, 0, 1) at (0, 0, 0) in component "Crossing mounts"
component "5537T586" placed x (1, 0, 0) y (0, 1, 0) z (0, 0, 1) at (0, 0, 0) in component "Crossing mounts"
component "PRT-SHIM" placed x (1, 0, 0) y (0, 1, 0) z (0, 0, 1) at (0, 0, 0) in component "Crossing mounts"
component "5537T586" placed x (1, 0, 0) y (0, 1, 0) z (0, 0, 1) at (0, 0, 0) in component "Crossing mounts"
component "PRT-SHIM" placed x (1, 0, 0) y (0, 1, 0) z (0, 0, 1) at (0, 0, 0) in component "Crossing mounts"
component "5537T586" placed x (1, 0, 0) y (0, 1, 0) z (0, 0, 1) at (0, 0, 0) in component "Crossing mounts"
component "PRT-SHIM" placed x (1, 0, 0) y (0, 1, 0) z (0, 0, 1) at (0, 0, 0) in component "Crossing mounts"
component "5537T586" placed x (1, 0, 0) y (0, 1, 0) z (0, 0, 1) at (0, 0, 0) in component "Crossing mounts"
component "PRT-SHIM" placed x (1, 0, 0) y (0, 1, 0) z (0, 0, 1) at (0, 0, 0) in component "Crossing mounts"
component "5537T586" placed x (1, 0, 0) y (0, 1, 0) z (0, 0, 1) at (0, 0, 0) in component "Crossing mounts"
component "PRT-SHIM" placed x (1, 0, 0) y (0, 1, 0) z (0, 0, 1) at (0, 0, 0) in component "Crossing mounts"
component "5537T586" placed x (1, 0, 0) y (0, 1, 0) z (0, 0, 1) at (0, 0, 0) in component "Crossing mounts"
component "PRT-SHIM" placed x (1, 0, 0) y (0, 1, 0) z (0, 0, 1) at (0, 0, 0) in component "Crossing mounts"
component "5537T586" placed x (1, 0, 0) y (0, 1, 0) z (0, 0, 1) at (0, 0, 0) in component "Crossing mounts"
component "PRT-SHIM" placed x (1, 0, 0) y (0, 1, 0) z (0, 0, 1) at (0, 0, 0) in component "Crossing mounts"
component "5537T586" placed x (1, 0, 0) y (0, 1, 0) z (0, 0, 1) at (0, 0, 0) in component "Crossing mounts"
component "PRT-SHIM" placed x (1, 0, 0) y (0, 1, 0) z (0, 0, 1) at (0, 0, 0) in component "Crossing mounts"
component "5537T586" placed x (1, 0, 0) y (0, 1, 0) z (0, 0, 1) at (0, 0, 0) in component "Crossing mounts"
component "PRT-SHIM" placed x (1, 0, 0) y (0, 1, 0) z (0, 0, 1) at (0, 0, 0) in component "Crossing mounts"
component "5537T586" placed x (1, 0, 0) y (0, 1, 0) z (0, 0, 1) at (0, 0, 0) in component "Crossing mounts"
component "PRT-SHIM" placed x (1, 0, 0) y (0, 1, 0) z (0, 0, 1) at (0, 0, 0) in component "Crossing mounts"
component "5537T586" placed x (1, 0, 0) y (0, 1, 0) z (0, 0, 1) at (0, 0, 0) in component "Crossing mounts"
component "PRT-SHIM" placed x (1, 0, 0) y (0, 1, 0) z (0, 0, 1) at (0, 0, 0) in component "Crossing mounts"
component "5537T586" placed x (1, 0, 0) y (0, 1, 0) z (0, 0, 1) at (0, 0, 0) in component "Crossing mounts"
component "PRT-SHIM" placed x (1, 0, 0) y (0, 1, 0) z (0, 0, 1) at (0, 0, 0) in component "Crossing mounts"
component "5537T586" placed x (1, 0, 0) y (0, 1, 0) z (0, 0, 1) at (0, 0, 0) in component "Crossing mounts"
component "PRT-SHIM" placed x (1, 0, 0) y (0, 1, 0) z (0, 0, 1) at (0, 0, 0) in component "Crossing mounts"
component "5537T586" placed x (1, 0, 0) y (0, 1, 0) z (0, 0, 1) at (0, 0, 0) in component "Crossing mounts"
component "PRT-SHIM" placed x (1, 0, 0) y (0, 1, 0) z (0, 0, 1) at (0, 0, 0) in component "Crossing mounts"
component "5537T586" placed x (1, 0, 0) y (0, 1, 0) z (0, 0, 1) at (0, 0, 0) in component "Crossing mounts"
component "PRT-SHIM" placed x (1, 0, 0) y (0, 1, 0) z (0, 0, 1) at (0, 0, 0) in component "Crossing mounts"
component "6575N25 x 100" placed x (1, 0, 0) y (0, 1, 0) z (0, 0, 1) at (0, 0, 0) in component "Stand"
component "5537T983" placed x (1, 0, 0) y (0, 1, 0) z (0, 0, 1) at (0, 0, 0) in component "Stand"
component "5537T586" placed x (1, 0, 0) y (0, 1, 0) z (0, 0, 1) at (0, 0, 0) in component "Stand"
component "5537T586" placed x (1, 0, 0) y (0, 1, 0) z (0, 0, 1) at (0, 0, 0) in component "Stand"
component "6575N25 x 100" placed x (1, 0, 0) y (0, 1, 0) z (0, 0, 1) at (0, 0, 0) in component "Stand"
component "5537T983" placed x (1, 0, 0) y (0, 1, 0) z (0, 0, 1) at (0, 0, 0) in component "Stand"
component "5537T586" placed x (1, 0, 0) y (0, 1, 0) z (0, 0, 1) at (0, 0, 0) in component "Stand"
component "5537T586" placed x (1, 0, 0) y (0, 1, 0) z (0, 0, 1) at (0, 0, 0) in component "Stand"
component "6575N25 x 100" placed x (1, 0, 0) y (0, 1, 0) z (0, 0, 1) at (0, 0, 0) in component "Stand"
component "5537T983" placed x (1, 0, 0) y (0, 1, 0) z (0, 0, 1) at (0, 0, 0) in component "Stand"
component "5537T586" placed x (1, 0, 0) y (0, 1, 0) z (0, 0, 1) at (0, 0, 0) in component "Stand"
component "5537T586" placed x (1, 0, 0) y (0, 1, 0) z (0, 0, 1) at (0, 0, 0) in component "Stand"
component "6575N25 x 100" placed x (1, 0, 0) y (0, 1, 0) z (0, 0, 1) at (0, 0, 0) in component "Stand"
component "5537T983" placed x (1, 0, 0) y (0, 1, 0) z (0, 0, 1) at (0, 0, 0) in component "Stand"
component "5537T586" placed x (1, 0, 0) y (0, 1, 0) z (0, 0, 1) at (0, 0, 0) in component "Stand"
component "5537T586" placed x (1, 0, 0) y (0, 1, 0) z (0, 0, 1) at (0, 0, 0) in component "Stand"
component "6575N25 x 682.5" placed x (1, 0, 0) y (0, 1, 0) z (0, 0, 1) at (0, 0, 0) in component "CubeSat hanger"
component "5537T586" placed x (1, 0, 0) y (0, 1, 0) z (0, 0, 1) at (0, 0, 0) in component "CubeSat hanger"
component "5537T586" placed x (1, 0, 0) y (0, 1, 0) z (0, 0, 1) at (0, 0, 0) in component "CubeSat hanger"
component "5537T586" placed x (1, 0, 0) y (0, 1, 0) z (0, 0, 1) at (0, 0, 0) in component "CubeSat hanger"
component "5537T586" placed x (1, 0, 0) y (0, 1, 0) z (0, 0, 1) at (0, 0, 0) in component "CubeSat hanger"
component "PRT-HANGER" placed x (1, 0, 0) y (0, 1, 0) z (0, 0, 1) at (0, 0, 0) in component "CubeSat hanger"
component "Sling cord" placed x (1, 0, 0) y (0, 1, 0) z (0, 0, 1) at (0, 0, 0) in component "CubeSat hanger"
component "PRT-TRAY" placed x (1, 0, 0) y (0, 1, 0) z (0, 0, 1) at (0, 0, 0) in component "CubeSat hanger"
component "6U envelope (reference)" placed x (1, 0, 0) y (0, 1, 0) z (0, 0, 1) at (0, 0, 0) in component "Reference (not built)"
component "Working volume 6U+10 (reference)" placed x (1, 0, 0) y (0, 1, 0) z (0, 0, 1) at (0, 0, 0) in component "Reference (not built)"
component "PRT-GAUGE-X" placed x (1, 0, 0) y (0, 1, 0) z (0, 0, 1) at (0, 0, 0) in component "Assembly gauges (removable)"
component "PRT-GAUGE-Y" placed x (1, 0, 0) y (0, 1, 0) z (0, 0, 1) at (0, 0, 0) in component "Assembly gauges (removable)"
component "PRT-GAUGE-Z" placed x (1, 0, 0) y (0, 1, 0) z (0, 0, 1) at (0, 0, 0) in component "Assembly gauges (removable)"
component "PRT-GAUGE-C" placed x (1, 0, 0) y (0, 1, 0) z (0, 0, 1) at (0, 0, 0) in component "Assembly gauges (removable)"
equation "prof = 40 mm" comment "Rail size (McMaster 6575N25, 8 mm slot)"
equation "e_c = 10 mm" comment "Winding centroid depth below the outer rail face (hex-nested 9/10/11/10 rows of 18 AWG give 10.04)"
equation "gap = 2 mm" comment "Assembly clearance between nested coil frames, filled by PRT-SHIM at each crossing"
equation "X_side = 1361 mm" comment "X coil mean-turn side (simulator)"
equation "Y_side = 1445 mm" comment "Y coil mean-turn side (simulator)"
equation "Z_side = 1529 mm" comment "Z coil mean-turn side (simulator)"
equation "X_spacing = 722.5 mm" comment "X pair coil-centre spacing"
equation "Y_spacing = 767 mm" comment "Y pair coil-centre spacing"
equation "Z_spacing = 850 mm" comment "Z pair coil-centre spacing"
equation "X_F = X_side / 2 + e_c" comment "X coil outer face half-width"
equation "Y_F = Y_side / 2 + e_c" comment "Y coil outer face half-width"
equation "Z_F = Z_side / 2 + e_c" comment "Z coil outer face half-width"
equation "slot_open = 8 mm" comment "Slot opening"
equation "slot_lip = 4.5 mm" comment "Slot lip thickness (measured from drawing)"
equation "slot_cav_w = 22 mm" comment "Slot cavity width"
equation "slot_taper = 6.8 mm" comment "Depth where the cavity starts tapering (measured from drawing)"
equation "slot_floor_w = 11.2 mm" comment "Slot floor width (measured from drawing)"
equation "slot_cav_d = 12.2 mm" comment "Slot depth"
equation "core_d = 7 mm" comment "Rail centre bore"
equation "wire_od = 1.10 mm" comment "AWG 18 heavy-build wire OD (maximum)"
equation "row_p = wire_od * sqrt(3) / 2" comment "Row-to-row pitch of hex-nested rows"
equation "liner_t = 0.13 mm" comment "Nomex slot liner"
equation "wind_floor = slot_cav_d - liner_t" comment "Winding floor depth below the outer face"
equation "r_floor = 12 mm" comment "Corner groove floor radius"
equation "nest_clr = 0.15 mm" comment "Corner nest: gap from each row's end turn to its terrace wall"
equation "nest_v = wire_od * ( 1 / sqrt(3) - 0.5 )" comment "Corner nest: V-groove valley below wind_floor (row-0 turns sit at the rail's depth)"
equation "nest_ridge = wire_od / ( 2 * sqrt(3) )" comment "Corner nest: V-groove depth (120 deg grooves at wire pitch)"
equation "cheek_t = 8 mm" comment "Printed corner cheek thickness"
equation "cheek_leg = 60 mm" comment "Printed corner cheek leg length"
equation "brk_leg = 40.6 mm" comment "Gusset 5537T586 leg, 1.6 in (McMaster drawing)"
equation "brk_t = 6 mm" comment "Gusset wall thickness (not on the McMaster drawing; assumed)"
equation "brk_w = 36 mm" comment "Gusset width (McMaster drawing)"
equation "brk_hole = 20 mm" comment "Gusset hole centre from the corner (McMaster drawing)"
equation "hole_d = 9 mm" comment "Gusset mounting hole, M8 (size assumed)"
equation "hole_m6 = 6.6 mm" comment "M6 clearance hole in printed parts"
equation "cbore_d = 11.5 mm" comment "Counterbore for an M6 button head in printed parts"
equation "cbore_grip = 5 mm" comment "Printed material left under an M6 head, so a 16 mm screw reaches its hammer nut"
equation "clip_w = 15 mm" comment "Clip width along the rail"
equation "clip_t = 2.5 mm" comment "Clip bridge thickness (sets the downforce)"
equation "clip_arm = 2.5 mm" comment "Clip arm thickness"
equation "clip_clr = 0.15 mm" comment "Clip arm clearance to the rail side face"
equation "clip_hook = 1.35 mm" comment "Hook overhang past the arm (about 1.2 mm into the side-slot opening)"
equation "clip_tongue = wind_floor - wire_od - 3 * row_p - 0.3 mm" comment "Tongue depth below the rail face: top of the 4th row + 0.3 mm preload (7.81)"
equation "sat_x = 100 mm" comment "6U envelope x"
equation "sat_y = 226.3 mm" comment "6U envelope y"
equation "sat_z = 366 mm" comment "6U envelope z (long axis along cage Z)"
equation "wv_margin = 10 mm" comment "Working volume margin around the 6U envelope"
equation "cradle_t = 8 mm" comment "Printed satellite tray thickness"
equation "sling_x = 66 mm" comment "Sling cord x (just outside the working volume)"
equation "sling_y = 100 mm" comment "Sling cord y at the tray"
equation "cord_d = 3 mm" comment "Sling cord width"
equation "hanger_t = 12 mm" comment "Printed spreader thickness"
equation "leg_x = 560 mm" comment "Leg x position on the bottom Y members"
equation "leg_l = 100 mm" comment "Rail stub length, cut from offcuts"
equation "L_mem_X = 2 * ( X_F - prof )" comment "Cut length: X coil member"
equation "L_mem_Y = 2 * ( Y_F - prof )" comment "Cut length: Y coil member"
equation "L_mem_Z = 2 * ( Z_F - prof )" comment "Cut length: Z coil member"
equation "L_beam = X_spacing - prof" comment "Cut length: satellite beam between the X coils"
equation "leg_z = -( Y_F - prof ) - leg_l" comment "Rail stub bottom (z)"
equation "tray_z = -sat_z / 2 - cradle_t" comment "Tray underside (z); tray top = 6U bottom face"
equation "L_g_X = ( Y_F - prof - cheek_leg ) - ( X_spacing / 2 + prof / 2 )" comment "Gauge: X coil position on a Y member"
equation "L_g_Y = ( Z_F - prof - cheek_leg ) - ( Y_spacing / 2 + prof / 2 )" comment "Gauge: Y coil position on a Z member"
equation "L_g_Z = ( Y_F - prof - cheek_leg ) - ( Z_spacing / 2 + prof / 2 )" comment "Gauge: Z coil position on a Y member"
equation "L_g_C = ( X_F - prof - cheek_leg ) - ( Y_spacing / 2 + prof / 2 )" comment "Gauge: X coil centring on its own member"
equation "L_leg = leg_l" comment "Cut length: rail stub leg"
equation "d66 = 0.5 * prof"
equation "d67 = 0.5 * slot_open"
equation "d68 = 0.5 * prof - slot_lip"
equation "d69 = 0.5 * slot_cav_w"
equation "d70 = 0.5 * prof - slot_cav_d"
equation "d71 = 0.5 * slot_cav_w"
equation "d72 = 0.5 * prof - slot_lip"
equation "d73 = 0.5 * slot_open"
equation "d74 = 0.5 * prof"
equation "d75 = 0.5 * prof"
equation "d76 = 0.5 * slot_open"
equation "d77 = 0.5 * prof - slot_lip"
equation "d78 = 0.5 * slot_cav_w"
equation "d79 = 0.5 * prof - slot_cav_d"
equation "d80 = 0.5 * slot_cav_w"
equation "d81 = 0.5 * prof - slot_lip"
equation "d82 = 0.5 * slot_open"
equation "d83 = 0.5 * prof"
equation "d84 = 0.5 * prof"
equation "d85 = 0.5 * slot_open"
equation "d86 = 0.5 * prof - slot_lip"
equation "d87 = 0.5 * slot_cav_w"
equation "d88 = 0.5 * prof - slot_cav_d"
equation "d89 = 0.5 * slot_cav_w"
equation "d90 = 0.5 * prof - slot_lip"
equation "d91 = 0.5 * slot_open"
equation "d92 = 0.5 * prof"
equation "d93 = 0.5 * prof"
equation "d94 = 0.5 * slot_open"
equation "d95 = 0.5 * prof - slot_lip"
equation "d96 = 0.5 * slot_cav_w"
equation "d97 = 0.5 * prof - slot_cav_d"
equation "d98 = 0.5 * slot_cav_w"
equation "d99 = 0.5 * prof - slot_lip"
equation "d100 = 0.5 * slot_open"
equation "d101 = 0.5 * prof"
equation "d102 = 0.5 * prof - slot_taper"
equation "d103 = 0.5 * slot_floor_w"
equation "d104 = 0.5 * slot_floor_w"
equation "d105 = 0.5 * prof - slot_taper"
equation "d106 = 0.5 * prof - slot_taper"
equation "d107 = 0.5 * slot_floor_w"
equation "d108 = 0.5 * slot_floor_w"
equation "d109 = 0.5 * prof - slot_taper"
equation "d110 = 0.5 * prof - slot_taper"
equation "d111 = 0.5 * slot_floor_w"
equation "d112 = 0.5 * slot_floor_w"
equation "d113 = 0.5 * prof - slot_taper"
equation "d114 = 0.5 * prof - slot_taper"
equation "d115 = 0.5 * slot_floor_w"
equation "d116 = 0.5 * slot_floor_w"
equation "d117 = 0.5 * prof - slot_taper"
equation "d118 = core_d"
equation "d119 = L_mem_X"
equation "d121 = prof"
equation "d122 = prof"
equation "d123 = -0.5 * prof"
equation "d124 = prof"